Autodesk Fusion 360 part; units mm, degrees
(part 2 of 2)
ref_plane "WorkPlane4" through (0, 0, 55) normal (0, 0, 1) x (1, 0, 0) in component "REFERENCE - six mount pads - compressed"
sketch "right lower-ledge pad - 20 x 10 x 3 outline" plane through (0, 0, 55) normal (0, 0, 1) x (1, 0, 0) in component "REFERENCE - six mount pads - compressed"
  line L0 (179, 0.5) -> (199, 0.5)
  line L1 (199, 0.5) -> (199, 10.5)
  line L2 (199, 10.5) -> (179, 10.5)
  line L3 (179, 10.5) -> (179, 0.5)
extrude "right lower-ledge pad - 20 x 10 x 3" add sketch "right lower-ledge pad - 20 x 10 x 3 outline" along normal blind 2.5 separate body makes body 22 in component "REFERENCE - six mount pads - compressed"
ref_plane "WorkPlane5" through (0, 0, 67) normal (0, 0, 1) x (1, 0, 0) in component "REFERENCE - six mount pads - compressed"
sketch "right upper-ledge pad - 20 x 9 x 3 outline" plane through (0, 0, 67) normal (0, 0, 1) x (1, 0, 0) in component "REFERENCE - six mount pads - compressed"
  line L0 (179, 13) -> (199, 13)
  line L1 (199, 13) -> (199, 22)
  line L2 (199, 22) -> (179, 22)
  line L3 (179, 22) -> (179, 13)
extrude "right upper-ledge pad - 20 x 9 x 3" add sketch "right upper-ledge pad - 20 x 9 x 3 outline" along normal blind 2.5 separate body makes body 23 in component "REFERENCE - six mount pads - compressed"
ref_plane "WorkPlane6" through (0, 0, -2.5) normal (0, 0, 1) x (1, 0, 0) in component "REFERENCE - six mount pads - compressed"
sketch "right underside retaining pad - 16 x 14 x 3 outline" plane through (0, 0, -2.5) normal (0, 0, 1) x (1, 0, 0) in component "REFERENCE - six mount pads - compressed"
  line L0 (181, 30) -> (197, 30)
  line L1 (197, 30) -> (197, 44)
  line L2 (197, 44) -> (181, 44)
  line L3 (181, 44) -> (181, 30)
extrude "right underside retaining pad - 16 x 14 x 3" add sketch "right underside retaining pad - 16 x 14 x 3 outline" along normal blind 2.5 separate body makes body 24 in component "REFERENCE - six mount pads - compressed"
ref_plane "WorkPlane1" through (-10, 0, 0) normal (1, 0, 0) x (0, 1, 0) in component "REFERENCE - upward-stepped frame - back wall assumed"
sketch "Corrected upward frame outline" plane through (-10, 0, 0) normal (1, 0, 0) x (0, 0, -1) in component "REFERENCE - upward-stepped frame - back wall assumed"
  line L0 (0, 0) -> (0, 52)
  line L1 (0, 52) -> (-180, 52)
  line L2 (-180, 52) -> (-180, 23)
  line L3 (-180, 23) -> (-67, 23)
  line L4 (-67, 23) -> (-67, 12)
  line L5 (-67, 12) -> (-55, 12)
  line L6 (-55, 12) -> (-55, 0)
  line L7 (-55, 0) -> (0, 0)
extrude "Corrected upward frame" add sketch "Corrected upward frame outline" along normal blind 234 separate body makes body 25 in component "REFERENCE - upward-stepped frame - back wall assumed"
ref_plane "WorkPlane1" through (245, 0, 0) normal (1, 0, 0) x (0, 1, 0) in component "07 Upward-step fit gauge PRINT FIRST - PRINT"
sketch "Profile fit gauge outline" plane through (245, 0, 0) normal (1, 0, 0) x (0, 0, -1) in component "07 Upward-step fit gauge PRINT FIRST - PRINT"
  line L0 (0, -0.6) -> (-55.6, -0.6)
  line L1 (-55.6, -0.6) -> (-55.6, 11.4)
  line L2 (-55.6, 11.4) -> (-67.6, 11.4)
  line L3 (-67.6, 11.4) -> (-67.6, 23)
  line L4 (-67.6, 23) -> (-70, 23)
  line L5 (-70, 23) -> (-70, 9)
  line L6 (-70, 9) -> (-58, 9)
  line L7 (-58, 9) -> (-58, -3)
  line L8 (-58, -3) -> (0, -3)
  line L9 (0, -3) -> (0, -0.6)
extrude "Profile fit gauge" add sketch "Profile fit gauge outline" along normal blind 8 separate body makes body 26 in component "07 Upward-step fit gauge PRINT FIRST - PRINT"
ref_plane "WorkPlane6" through (12, 0, 0) normal (1, 0, 0) x (0, 1, 0) in component "03 left passive retaining saddle - PRINT"
sketch "Flat print side A outline" plane through (12, 0, 0) normal (1, 0, 0) x (0, 0, -1) in component "03 left passive retaining saddle - PRINT"
  line L0 (7, -11) -> (7, 45)
  line L1 (7, 45) -> (2, 45)
  line L2 (2, 45) -> (2, -1)
  line L3 (2, -1) -> (-7, -6)
  line L4 (-7, -6) -> (-66, -6)
  line L5 (-66, -6) -> (-66, -11)
  line L6 (-66, -11) -> (7, -11)
extrude "Flat print side A" add sketch "Flat print side A outline" along normal blind 3 bodies 16 in component "03 left passive retaining saddle - PRINT"
ref_plane "WorkPlane7" through (35, 0, 0) normal (1, 0, 0) x (0, 1, 0) in component "03 left passive retaining saddle - PRINT"
sketch "Flat print side B outline" plane through (35, 0, 0) normal (1, 0, 0) x (0, 0, -1) in component "03 left passive retaining saddle - PRINT"
  line L0 (7, -11) -> (7, 45)
  line L1 (7, 45) -> (2, 45)
  line L2 (2, 45) -> (2, -1)
  line L3 (2, -1) -> (-7, -6)
  line L4 (-7, -6) -> (-66, -6)
  line L5 (-66, -6) -> (-66, -11)
  line L6 (-66, -11) -> (7, -11)
extrude "Flat print side B" add sketch "Flat print side B outline" along normal blind 3 bodies 16 in component "03 left passive retaining saddle - PRINT"
ref_plane "WorkPlane8" through (11.9, 0, 0) normal (1, 0, 0) x (0, 1, 0) in component "03 left passive retaining saddle - PRINT"
sketch "Full-width entry chamfer outline" plane through (11.9, 0, 0) normal (1, 0, 0) x (0, 0, -1) in component "03 left passive retaining saddle - PRINT"
  line L0 (2, 44.5) -> (2, 45)
  line L1 (2, 45) -> (2.5, 45)
  line L2 (2.5, 45) -> (2, 44.5)
extrude "Full-width entry chamfer" cut sketch "Full-width entry chamfer outline" along normal blind 26.2 bodies 16 in component "03 left passive retaining saddle - PRINT"
ref_plane "WorkPlane6" through (176, 0, 0) normal (1, 0, 0) x (0, 1, 0) in component "03 right passive retaining saddle - PRINT"
sketch "Flat print side A outline (2)" plane through (176, 0, 0) normal (1, 0, 0) x (0, 0, -1) in component "03 right passive retaining saddle - PRINT"
  line L0 (7, -11) -> (7, 45)
  line L1 (7, 45) -> (2, 45)
  line L2 (2, 45) -> (2, -1)
  line L3 (2, -1) -> (-7, -6)
  line L4 (-7, -6) -> (-66, -6)
  line L5 (-66, -6) -> (-66, -11)
  line L6 (-66, -11) -> (7, -11)
extrude "Flat print side A'" add sketch "Flat print side A outline (2)" along normal blind 3 bodies 17 in component "03 right passive retaining saddle - PRINT"
ref_plane "WorkPlane7" through (199, 0, 0) normal (1, 0, 0) x (0, 1, 0) in component "03 right passive retaining saddle - PRINT"
sketch "Flat print side B outline (2)" plane through (199, 0, 0) normal (1, 0, 0) x (0, 0, -1) in component "03 right passive retaining saddle - PRINT"
  line L0 (7, -11) -> (7, 45)
  line L1 (7, 45) -> (2, 45)
  line L2 (2, 45) -> (2, -1)
  line L3 (2, -1) -> (-7, -6)
  line L4 (-7, -6) -> (-66, -6)
  line L5 (-66, -6) -> (-66, -11)
  line L6 (-66, -11) -> (7, -11)
extrude "Flat print side B'" add sketch "Flat print side B outline (2)" along normal blind 3 bodies 17 in component "03 right passive retaining saddle - PRINT"
ref_plane "WorkPlane8" through (175.9, 0, 0) normal (1, 0, 0) x (0, 1, 0) in component "03 right passive retaining saddle - PRINT"
sketch "Full-width entry chamfer outline (2)" plane through (175.9, 0, 0) normal (1, 0, 0) x (0, 0, -1) in component "03 right passive retaining saddle - PRINT"
  line L0 (2, 44.5) -> (2, 45)
  line L1 (2, 45) -> (2.5, 45)
  line L2 (2.5, 45) -> (2, 44.5)
extrude "Full-width entry chamfer'" cut sketch "Full-width entry chamfer outline (2)" along normal blind 26.2 bodies 17 in component "03 right passive retaining saddle - PRINT"
component "REFERENCE - INIU P51L-E2 115 x 73 x 29 mm" placed x (1, 0, 0) y (0, 0, -1) z (0, 1, 0) at (70, -14, 156.5)
component "REFERENCE - Raspberry Pi4 rotated ports" placed x (0, 0, 1) y (-1, 0, 0) z (0, -1, 0) at (77, 60, 69)
component "04 Camera G carrier - PRINT" placed x (-1, 0, 0) y (0, 1, 0) z (0, 0, -1) at (126, -21.65, -8)
component "05 Camera G protective cap - PRINT" placed x (-1, 0, 0) y (0, 1, 0) z (0, 0, -1) at (126, -21.65, -8)
component "REFERENCE - Waveshare RPi Camera G PCB and lens" placed x (-1, 0, 0) y (0, 1, 0) z (0, 0, -1) at (126, -21.65, -8)
component "01 Upright Pi and battery shell - PRINT" placed x (1, 0, 0) y (0, 1, 0) z (0, 0, 1) at (0, 0, 0)
component "02 Vented front service panel - PRINT" placed x (1, 0, 0) y (0, 1, 0) z (0, 0, 1) at (0, 0, 0)
component "03 left passive retaining saddle - PRINT" placed x (1, 0, 0) y (0, 1, 0) z (0, 0, 1) at (0, 0, 0)
component "03 right passive retaining saddle - PRINT" placed x (1, 0, 0) y (0, 1, 0) z (0, 0, 1) at (0, 0, 0)
component "06 Straight-down camera support - PRINT" placed x (1, 0, 0) y (0, 1, 0) z (0, 0, 1) at (0, 0, 0)
component "REFERENCE - six mount pads - compressed" placed x (1, 0, 0) y (0, 1, 0) z (0, 0, 1) at (0, 0, 0)
component "REFERENCE - upward-stepped frame - back wall assumed" placed x (1, 0, 0) y (0, 1, 0) z (0, 0, 1) at (0, 0, 0)
component "07 Upward-step fit gauge PRINT FIRST - PRINT" placed x (1, 0, 0) y (0, 1, 0) z (0, 0, 1) at (0, 0, 0)
equation "wall = 2.4 mm" comment "Printed shell wall and tray thickness"
equation "battery_tray_height = 37 mm" comment "Battery chamber outside height"
equation "upper_height = 32 mm" comment "Pi chamber height above battery tray"
equation "lid_thickness = 2.4 mm" comment "Removable lid"
equation "pi_standoff_height = 5 mm" comment "Pi underside clearance"
equation "pad_recess_depth = 0.8 mm" comment "Use 3 mm rubber pads; 2.2 mm projects below case"
equation "camera_carrier_thickness = 3 mm" comment "Camera backplate"
equation "camera_standoff_height = 2.5 mm" comment "Clearance under camera PCB"
equation "camera_lens_opening = 22 mm" comment "Generous opening; check actual lens barrel before final print"
equation "camera_cap_height = 17 mm" comment "Cap height above carrier; lens must project beyond the front"
equation "d177 = camera_carrier_thickness"
equation "d181 = camera_standoff_height"
equation "d193 = camera_cap_height"
equation "d201 = camera_lens_opening"
named bodies: "INIU envelope - check supplied cable position", "Pi PCB 85 x 56 x 1.6", "USB3", "USB2", "Ethernet", "USB-C", "HDMI0", "HDMI1", "Audio", "Camera carrier", "Camera cap shell", "Camera PCB 25 x 24", "Upright open-front shell", "Removable front panel", "Camera support plate", "left lower-ledge pad - 20 x 10 x 3", "left upper-ledge pad - 20 x 9 x 3", "left underside retaining pad - 16 x 14 x 3", "right lower-ledge pad - 20 x 10 x 3", "right upper-ledge pad - 20 x 9 x 3", "right underside retaining pad - 16 x 14 x 3"
